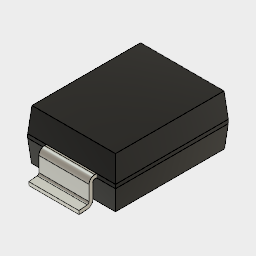
Untitled v1 (Autodesk Fusion 360 archive; units mm, degrees)
design "TSOP-2 4mm"
Autodesk Fusion 360 part; units mm, degrees
ref_plane "WorkPlane1" through (0, 0, 0.925) normal (0, 0, 1) x (1, 0, 0)
sketch "Sketch1" plane through (0, 0, 0.925) normal (0, 0, 1) x (1, 0, 0)
  line L0 (1.75, 2.25) -> (-1.75, 2.25)
  line L1 (-1.75, 2.25) -> (-1.75, -2.25)
  line L2 (-1.75, -2.25) -> (1.75, -2.25)
  line L3 (1.75, -2.25) -> (1.75, 2.25)
  line L4 (1.75, 2.25) -> (-1.75, -2.25) construction
  line L5 (-1.75, 2.25) -> (1.75, -2.25) construction
  dimension "d2" = 3.5
  dimension "d3" = 4.5
  measures "d2" distance of L1.end L2.end
  measures "d3" distance of L0.end L1.end
extrude "Extrude1" add sketch "Sketch1" against normal blind 0.875 draft -5 makes body 1
extrude "Extrude3" add sketch "Sketch1" along normal blind 0.15 bodies 1
extrude "Extrude4" add sketch "Sketch1" along normal blind 0.975 draft -5 from surface at 0.15 bodies 1
sketch "Sketch2" plane through (0, -2.25, 0) normal (0, -1, 0) x (1, 0, 0)
  line L0 (1.4672, 0.1123) -> (1.5, 0.4887)
  line L1 (1, 0.925) -> (-1, 0.925)
  line L2 (-1, 0.925) -> (-1, 1.075)
  line L3 (-1, 1.075) -> (1, 1.075)
  line L4 (1, 1.075) -> (1, 0.925)
  line L5 (1, 0.925) -> (-1, 1.075) construction
  line L6 (-1, 0.925) -> (1, 1.075) construction
  line L7 (-1.75, 0.925) -> (1.75, 0.925)
  line L8 (1.75, 0.925) -> (1.75, 1.075)
  line L9 (1.75, 1.075) -> (-1.75, 1.075)
  line L10 (-1.75, 1.075) -> (-1.75, 0.925)
  point P0 (0, 1)
  dimension "d6" = 2
  dimension "d7" = 0.15
  dimension "d51" = 1
  measures "d6" distance of L2.end L3.end
  measures "d7" distance of L1.end L2.end
  measures "d51" distance of origin P0
sketch "Sketch3" plane through (0, 0, 0) normal (1, 0, 0) x (0, 1, 0)
  line L0 (-2.25, 1) -> (-2.325, 1)
  arc A0 (-2.325, 1) -> (-2.475, 0.85) centre (-2.325, 0.85) ccw
  line L1 (-2.475, 0.85) -> (-2.475, 0.254)
  arc A1 (-2.6119, 0.1046) -> (-2.475, 0.254) centre (-2.625, 0.254) ccw
  line L2 (-2.6119, 0.1046) -> (-2.95, 0.075)
  line L3 (-2.25, 1.075) -> (-2.25, 0.925)
  line L4 (-2.25, 1) -> (-2.1, 1)
  line L5 (-2.95, 0.075) -> (-2.45, 0.075) construction
  point P0 (-2.25, 1)
  dimension "d10" = 0.15
  dimension "d11" = 0.075
  dimension "d21" = 0.15
  dimension "d22" = 0.225
  dimension "d23" = 0.7
  dimension "d24" = 0.5
  dimension "d25" = 5
  dimension "d26" = 0.15
  measures "d10" radius of A0
  measures "d11" distance of origin L2.end
  measures "d21" distance of P0 L4.end
  measures "d22" distance of P0 L1
  measures "d23" distance of P0 L2.end
  measures "d24" distance of L2.end L5.end
  measures "d25" angle of L2 L5
  measures "d26" radius of A1
sweep "Sweep1" add profiles "Sketch2" path "Sketch3" along L2 A1 L1 A0 L0 L4 section 1 contours L1 L2 L3 L4 L7 L9 separate body makes body 2
mirror "Mirror1" about plane through (0, 0, 0) normal (0, 1, 0) of "Sweep1" makes body 3
equation "d1 = tsop2_4_lead_attach - tsop2_4_lead_thickness / 2"
equation "d2 = tsop2_4_package_width"
equation "d3 = tsop2_4_package_depth"
equation "d4 = -tsop2_4_lead_attach + tsop2_4_lead_thickness / 2 + tsop2_4_above_board"
equation "d5 = -tsop2_4_package_taper"
equation "d6 = tsop2_4_lead_width"
equation "d7 = tsop2_4_lead_thickness"
equation "d10 = tsop2_4_lead_thickness"
equation "d11 = tsop2_4_lead_thickness / 2"
equation "tsop2_4_lead_thickness = 0.15 mm"
equation "tsop2_4_lead_attach = 1 mm"
equation "tsop2_4_lead_width = 2 mm"
equation "tsop2_4_lead_spacing = 1 mm"
equation "tsop2_4_package_width = 3.5 mm"
equation "tsop2_4_package_height = 2 mm"
equation "tsop2_4_package_depth = 4.5 mm"
equation "tsop2_4_above_board = 0.05 mm"
equation "d21 = tsop2_4_lead_into_package"
equation "d22 = tsop2_4_lead_thickness * ( 3 / 2 )"
equation "d23 = tsop2_4_lead_extension"
equation "d25 = tsop2_4_lead_foot_angle"
equation "d26 = d10"
equation "tsop2_4_lead_extension = 0.7 mm"
equation "tsop2_4_lead_foot_angle = 5 deg"
equation "tsop2_4_lead_into_package = 0.15 mm"
equation "tsop2_4_optional_lead_extension = 0 mm"
equation "tsop2_4_package_taper = 5 deg"
equation "d46 = tsop2_4_lead_thickness"
equation "d48 = tsop2_4_lead_thickness"
equation "d49 = tsop2_4_package_height - tsop2_4_lead_thickness / 2 - ( tsop2_4_lead_attach - tsop2_4_above_board )"
equation "d50 = -tsop2_4_package_taper"
equation "d51 = tsop2_4_lead_attach"
named bodies: "lead2", "opt_lead"

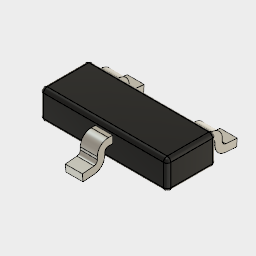
design "SOP-3 2.5mm"
Autodesk Fusion 360 part; units mm, degrees
ref_plane "WorkPlane1" through (0, 0, 0.05) normal (0, 0, 1) x (1, 0, 0)
sketch "Sketch1" plane through (0, 0, 0.05) normal (0, 0, 1) x (1, 0, 0)
  line L0 (1.3, 0.5) -> (-1.3, 0.5)
  line L1 (-1.3, 0.5) -> (-1.3, -0.5)
  line L2 (-1.3, -0.5) -> (1.3, -0.5)
  line L3 (1.3, -0.5) -> (1.3, 0.5)
  line L4 (1.3, 0.5) -> (-1.3, -0.5) construction
  line L5 (-1.3, 0.5) -> (1.3, -0.5) construction
  dimension "d2" = 2.6
  dimension "d3" = 1
  measures "d2" distance of L1.end L2.end
  measures "d3" distance of L0.end L1.end
extrude "Extrude1" add sketch "Sketch1" along normal blind 0.6 makes body 1
sketch "Sketch2" plane through (0, -0.5, 0) normal (0, -1, 0) x (1, 0, 0)
  line L0 (-1.3, 0.05) -> (1.3, 0.05)
  line L1 (1.3, 0.05) -> (1.3, 0.65)
  line L2 (1.3, 0.65) -> (-1.3, 0.65)
  line L3 (-1.3, 0.65) -> (-1.3, 0.05)
  line L4 (0.175, 0.375) -> (-0.175, 0.375)
  line L5 (-0.175, 0.375) -> (-0.175, 0.525)
  line L6 (-0.175, 0.525) -> (0.175, 0.525)
  line L7 (0.175, 0.525) -> (0.175, 0.375)
  line L8 (0.175, 0.375) -> (-0.175, 0.525) construction
  line L9 (-0.175, 0.375) -> (0.175, 0.525) construction
  point P0 (0, 0.45)
  dimension "d6" = 0.35
  dimension "d7" = 0.15
  dimension "d8" = 0.4
  measures "d6" distance of L5.end L6.end
  measures "d7" distance of L4.end L5.end
  measures "d8" distance of L0 P0
sketch "Sketch3" plane through (0, 0, 0) normal (1, 0, 0) x (0, 1, 0)
  line L0 (-0.5, 0.45) -> (-0.575, 0.45)
  arc A0 (-0.575, 0.45) -> (-0.725, 0.3) centre (-0.575, 0.3) ccw
  line L1 (-0.725, 0.3) -> (-0.725, 0.2453)
  arc A1 (-0.8619, 0.0958) -> (-0.725, 0.2453) centre (-0.875, 0.2453) ccw
  line L2 (-0.8619, 0.0958) -> (-1.1, 0.075)
  line L3 (-0.5, 0.525) -> (-0.5, 0.375)
  line L4 (-0.5, 0.45) -> (-0.4, 0.45)
  line L5 (-1.1, 0.075) -> (-0.6, 0.075) construction
  point P0 (-0.5, 0.45)
  dimension "d10" = 0.15
  dimension "d11" = 0.075
  dimension "d21" = 0.1
  dimension "d22" = 0.225
  dimension "d23" = 0.6
  dimension "d24" = 0.5
  dimension "d25" = 5
  dimension "d26" = 0.15
  measures "d10" radius of A0
  measures "d11" distance of origin L2.end
  measures "d21" distance of P0 L4.end
  measures "d22" distance of P0 L1
  measures "d23" distance of P0 L2.end
  measures "d24" distance of L2.end L5.end
  measures "d25" angle of L2 L5
  measures "d26" radius of A1
sweep "Sweep1" add profiles "Sketch2" path "Sketch3" along L2 A1 L1 A0 L0 L4 section 1 contours L4 L5 L6 L7 separate body makes body 2
pattern_linear "R-Pattern1" count 3 spacing 0.95 along (1, 0, 0) both ways of "Sweep1" makes body 3 at (-0.8917, -0.7997, 0.3107) makes body 4 at (1.0083, -0.7997, 0.3107)
fillet "Fillet1" radius 0.075 12 edges at (1.3, 0, 0.65) (0, -0.5, 0.65) (-1.3, 0, 0.65) (0, 0.5, 0.65) (1.3, -0.5, 0.35) (1.3, 0, 0.05) (1.3, 0.5, 0.35) (0, -0.5, 0.05) (-1.3, -0.5, 0.35) (-1.3, 0, 0.05) (0, 0.5, 0.05) (-1.3, 0.5, 0.35) on bodies 1
move_body "Move1" bodies 3 4 to x (-1, 0, 0) y (0, -1, 0) z (0, 0, 1) at (0, 0, 0)
equation "d1 = sop3_2_above_board"
equation "d2 = sop3_2_package_width"
equation "d3 = sop3_2_package_depth"
equation "d4 = sop3_2_package_height"
equation "d6 = sop3_2_lead_width"
equation "d7 = sop3_2_lead_thickness"
equation "d8 = sop3_2_lead_attach"
equation "d10 = sop3_2_lead_thickness"
equation "d11 = sop3_2_lead_thickness / 2"
equation "sop3_2_lead_thickness = 0.15 mm"
equation "sop3_2_lead_attach = 0.4 mm"
equation "sop3_2_lead_width = 0.35 mm"
equation "sop3_2_lead_spacing = 0.95 mm"
equation "sop3_2_package_width = 2.6 mm"
equation "sop3_2_package_height = 0.6 mm"
equation "sop3_2_package_depth = 1 mm"
equation "sop3_2_above_board = 0.05 mm"
equation "d21 = sop3_2_lead_into_package"
equation "d22 = sop3_2_lead_thickness * ( 3 / 2 )"
equation "d23 = sop3_2_lead_extension"
equation "d25 = sop3_2_lead_foot_angle"
equation "d26 = d10"
equation "sop3_2_lead_extension = 0.6 mm"
equation "sop3_2_lead_foot_angle = 5 deg"
equation "sop3_2_lead_into_package = 0.1 mm"
equation "d34 = sop3_2_lead_spacing"
equation "sop3_2_optional_lead_extension = 0 mm"
named bodies: "lead2", "lead1", "lead3"

design "SOP-3"
Autodesk Fusion 360 part; units mm, degrees
ref_plane "WorkPlane1" through (0, 0, 0.05) normal (0, 0, 1) x (1, 0, 0)
sketch "Sketch1" plane through (0, 0, 0.05) normal (0, 0, 1) x (1, 0, 0)
  line L0 (1.5, 0.75) -> (-1.5, 0.75)
  line L1 (-1.5, 0.75) -> (-1.5, -0.75)
  line L2 (-1.5, -0.75) -> (1.5, -0.75)
  line L3 (1.5, -0.75) -> (1.5, 0.75)
  line L4 (1.5, 0.75) -> (-1.5, -0.75) construction
  line L5 (-1.5, 0.75) -> (1.5, -0.75) construction
  dimension "d2" = 3
  dimension "d3" = 1.5
  measures "d2" distance of L1.end L2.end
  measures "d3" distance of L0.end L1.end
extrude "Extrude1" add sketch "Sketch1" along normal blind 1 makes body 1
sketch "Sketch2" plane through (0, -0.75, 0) normal (0, -1, 0) x (1, 0, 0)
  line L0 (-1.5, 0.05) -> (1.5, 0.05)
  line L1 (1.5, 0.05) -> (1.5, 1.05)
  line L2 (1.5, 1.05) -> (-1.5, 1.05)
  line L3 (-1.5, 1.05) -> (-1.5, 0.05)
  line L4 (0.175, 0.475) -> (-0.175, 0.475)
  line L5 (-0.175, 0.475) -> (-0.175, 0.625)
  line L6 (-0.175, 0.625) -> (0.175, 0.625)
  line L7 (0.175, 0.625) -> (0.175, 0.475)
  line L8 (0.175, 0.475) -> (-0.175, 0.625) construction
  line L9 (-0.175, 0.475) -> (0.175, 0.625) construction
  point P0 (0, 0.55)
  dimension "d6" = 0.35
  dimension "d7" = 0.15
  dimension "d8" = 0.5
  measures "d6" distance of L5.end L6.end
  measures "d7" distance of L4.end L5.end
  measures "d8" distance of L0 P0
sketch "Sketch3" plane through (0, 0, 0) normal (1, 0, 0) x (0, 1, 0)
  line L0 (-0.75, 0.55) -> (-0.825, 0.55)
  arc A0 (-0.825, 0.55) -> (-0.975, 0.4) centre (-0.825, 0.4) ccw
  line L1 (-0.975, 0.4) -> (-0.975, 0.2453)
  arc A1 (-1.1119, 0.0958) -> (-0.975, 0.2453) centre (-1.125, 0.2453) ccw
  line L2 (-1.1119, 0.0958) -> (-1.35, 0.075)
  line L3 (-0.75, 0.625) -> (-0.75, 0.475)
  line L4 (-0.75, 0.55) -> (-0.6, 0.55)
  line L5 (-1.35, 0.075) -> (-0.85, 0.075) construction
  point P0 (-0.75, 0.55)
  dimension "d10" = 0.15
  dimension "d11" = 0.075
  dimension "d21" = 0.15
  dimension "d22" = 0.225
  dimension "d23" = 0.6
  dimension "d24" = 0.5
  dimension "d25" = 5
  dimension "d26" = 0.15
  measures "d10" radius of A0
  measures "d11" distance of origin L2.end
  measures "d21" distance of P0 L4.end
  measures "d22" distance of P0 L1
  measures "d23" distance of P0 L2.end
  measures "d24" distance of L2.end L5.end
  measures "d25" angle of L2 L5
  measures "d26" radius of A1
sweep "Sweep1" add profiles "Sketch2" path "Sketch3" along L2 A1 L1 A0 L0 L4 section 1 contours L4 L5 L6 L7 separate body makes body 2
pattern_linear "R-Pattern1" count 3 spacing 0.95 along (1, 0, 0) both ways of "Sweep1" makes body 3 at (-1.0083, -1.049, 0.4214) makes body 4 at (0.8917, -1.049, 0.4214)
fillet "Fillet1" radius 0.075 12 edges at (1.5, 0, 1.05) (0, -0.75, 1.05) (-1.5, 0, 1.05) (0, 0.75, 1.05) (1.5, -0.75, 0.55) (1.5, 0, 0.05) (1.5, 0.75, 0.55) (0, -0.75, 0.05) (-1.5, -0.75, 0.55) (-1.5, 0, 0.05) (0, 0.75, 0.05) (-1.5, 0.75, 0.55) on bodies 1
move_body "Move1" bodies 3 4 to x (-1, 0, 0) y (0, -1, 0) z (0, 0, 1) at (0, 0, 0)
equation "d1 = sop3_above_board"
equation "d2 = sop3_package_width"
equation "d3 = sop3_package_depth"
equation "d4 = sop3_package_height"
equation "d6 = sop3_lead_width"
equation "d7 = sop3_lead_thickness"
equation "d8 = sop3_lead_attach"
equation "d10 = sop3_lead_thickness"
equation "d11 = sop3_lead_thickness / 2"
equation "sop3_lead_thickness = 0.15 mm"
equation "sop3_lead_attach = 0.5 mm"
equation "sop3_lead_width = 0.35 mm"
equation "sop3_lead_spacing = 0.95 mm"
equation "sop3_package_width = 3 mm"
equation "sop3_package_height = 1 mm"
equation "sop3_package_depth = 1.5 mm"
equation "sop3_above_board = 0.05 mm"
equation "d21 = sop3_lead_into_package"
equation "d22 = sop3_lead_thickness * ( 3 / 2 )"
equation "d23 = sop3_lead_extension"
equation "d25 = sop3_lead_foot_angle"
equation "d26 = d10"
equation "sop3_lead_extension = 0.6 mm"
equation "sop3_lead_foot_angle = 5 deg"
equation "sop3_lead_into_package = 0.15 mm"
equation "d34 = sop3_lead_spacing"
equation "sop3_optional_lead_extension = 0 mm"

design "capar2_1013"
Autodesk Fusion 360 part; units mm, degrees
ref_plane "WorkPlane4" through (0, 0, 0.02) normal (0, 0, 1) x (1, 0, 0)
sketch "Sketch5" plane through (0, 0, 0.02) normal (0, 0, 1) x (1, 0, 0)
  line L0 (0.65, -0.5) -> (-0.65, -0.5)
  line L1 (-0.65, -0.5) -> (-0.65, 0.5)
  line L2 (-0.65, 0.5) -> (0.65, 0.5)
  line L3 (0.65, 0.5) -> (0.65, -0.5)
  line L4 (0.65, -0.5) -> (-0.65, 0.5) construction
  line L5 (-0.65, -0.5) -> (0.65, 0.5) construction
  dimension "d38" = 1.3
  dimension "d39" = 1
  measures "d38" distance of L1.end L2.end
  measures "d39" distance of L0.end L1.end
extrude "Extrude4" add sketch "Sketch5" along normal blind 0.6 makes body 1
fillet "Fillet6" radius 0.03 12 edges at (-0.65, -0.5, 0.32) (-0.65, 0, 0.62) (0, 0.5, 0.62) (0, -0.5, 0.62) (-0.65, 0.5, 0.32) (-0.65, 0, 0.02) (0, -0.5, 0.02) (0, 0.5, 0.02) (0.65, 0, 0.62) (0.65, 0.5, 0.32) (0.65, -0.5, 0.32) (0.65, 0, 0.02) on bodies 1
sketch "Sketch7" plane through (0, 0, 0.02) normal (0, 0, 1) x (1, 0, 0)
  line L0 (-0.725, 0.4) -> (-0.275, 0.4)
  line L1 (-0.275, 0.4) -> (-0.275, 0.1)
  line L2 (-0.275, 0.1) -> (-0.725, 0.1)
  line L3 (-0.725, 0.1) -> (-0.725, 0.4)
  line L4 (0, 0) -> (-0.5, 0) construction
  line L5 (0, 0) -> (0, 0.4016) construction
  line L6 (-0.275, -0.4) -> (-0.275, -0.1)
  line L7 (-0.275, -0.1) -> (-0.725, -0.1)
  line L8 (-0.725, -0.1) -> (-0.725, -0.4)
  line L9 (-0.725, -0.4) -> (-0.275, -0.4)
  line L10 (0.725, 0.4) -> (0.275, 0.4)
  line L11 (0.275, 0.4) -> (0.275, 0.1)
  line L12 (0.275, 0.1) -> (0.725, 0.1)
  line L13 (0.725, 0.1) -> (0.725, 0.4)
  line L14 (0.725, -0.4) -> (0.275, -0.4)
  line L15 (0.275, -0.4) -> (0.275, -0.1)
  line L16 (0.725, -0.1) -> (0.725, -0.4)
  line L17 (0.275, -0.1) -> (0.725, -0.1)
  line L18 (-0.68, 0.4) -> (-0.68, 0.1)
  line L19 (-0.68, -0.1) -> (-0.68, -0.4)
  line L20 (-0.62, 0.4) -> (-0.62, 0.1)
  line L21 (-0.62, -0.1) -> (-0.62, -0.4)
  line L22 (0.68, 0.4) -> (0.68, 0.1)
  line L23 (0.62, 0.4) -> (0.62, 0.1)
  line L24 (0.68, -0.1) -> (0.68, -0.4)
  line L25 (0.62, -0.1) -> (0.62, -0.4)
  dimension "d41" = 0.45
  dimension "d42" = 0.3
  dimension "d43" = 1
  dimension "d44" = 0.5
  dimension "d45" = 0.62
  dimension "d46" = 0.06
  measures "d41" distance of L0.start L0.end
  measures "d42" distance of L0.start L2.end
  measures "d43" distance of L1 L13
  measures "d44" distance of L2 L9
  measures "d45" distance of L4.start L20
  measures "d46" distance of L18 L20
extrude "Extrude8" add sketch "Sketch7" against normal blind 0.02 separate body makes body 2 at (0.425, 0.3, 0.02) makes body 3 at (0.575, -0.3, 0.02) makes body 4 at (-0.575, 0.3, 0.02) makes body 5 at (-0.425, -0.3, 0.02)
extrude "Extrude9" add sketch "Sketch7" along normal blind 0.6 contours L0 L2 L18 L20 | L7 L9 L19 L21 | L10 L12 L22 L23 | L14 L17 L24 L25 bodies 2 3 4 5
sketch "Sketch6" plane through (0, 0, 0.62) normal (0, 0, 1) x (-1, 0, 0)
  line L0 (0, 0) -> (0.35, 0) construction
  line L1 (0, 0) -> (0, -0.4804) construction
  line L2 (0.68, 0.1) -> (0.48, 0.1)
  line L3 (0.48, 0.1) -> (0.48, 0.4)
  line L4 (0.48, 0.4) -> (0.68, 0.4)
  line L5 (0.68, 0.4) -> (0.68, 0.1)
  line L6 (0.68, -0.4) -> (0.68, -0.1)
  line L7 (0.68, -0.1) -> (0.48, -0.1)
  line L8 (0.48, -0.1) -> (0.48, -0.4)
  line L9 (0.48, -0.4) -> (0.68, -0.4)
  line L10 (-0.48, -0.1) -> (-0.48, -0.4)
  line L11 (-0.48, -0.4) -> (-0.68, -0.4)
  line L12 (-0.68, -0.4) -> (-0.68, -0.1)
  line L13 (-0.68, -0.1) -> (-0.48, -0.1)
  line L14 (-0.68, 0.4) -> (-0.68, 0.1)
  line L15 (-0.68, 0.1) -> (-0.48, 0.1)
  line L16 (-0.48, 0.4) -> (-0.68, 0.4)
  line L17 (-0.48, 0.1) -> (-0.48, 0.4)
  line L18 (0.68, 0.1) -> (0.68, 0.4)
  line L19 (0.68, 0.4) -> (0.62, 0.4)
  line L20 (0.62, 0.1) -> (0.68, 0.1)
  point P0 (0.68, 0.4)
  dimension "d51" = 0.2
  measures "d51" distance of L3 L5
extrude "Extrude7" add sketch "Sketch6" along normal blind 0.03 bodies 2 3 4 5
fillet "Fillet5" radius 0.3 4 edges at (0.68, 0.25, 0.02) (0.68, -0.25, 0.02) (-0.68, 0.25, 0.02) (-0.68, -0.25, 0.02) on bodies 2 3 4 5
fillet "Fillet5" radius 0.075 12 edges at (0.48, 0.1, 0.635) (0.48, 0.4, 0.635) (0.68, 0.25, 0.65) (0.68, -0.25, 0.65) (0.48, -0.4, 0.635) (0.48, -0.1, 0.635) (-0.68, 0.25, 0.65) (-0.48, 0.1, 0.635) (-0.48, 0.4, 0.635) (-0.48, -0.4, 0.635) (-0.48, -0.1, 0.635) (-0.68, -0.25, 0.65) on bodies 2 3 4 5
fillet "Fillet7" radius 0.02 44 edges at (0.6915, 0.1, 0.0959) (0.68, 0.1, 0.3765) (0.658, 0.1, 0.628) (0.58, 0.1, 0.65) (0.502, 0.122, 0.65) (0.48, 0.25, 0.65) (0.502, 0.378, 0.65) (0.58, 0.4, 0.65) (0.658, 0.4, 0.628) (0.68, 0.4, 0.3765) (0.6915, 0.4, 0.0959) (0.6915, -0.4, 0.0959) (0.68, -0.4, 0.3765) (0.658, -0.4, 0.628) (0.58, -0.4, 0.65) (0.502, -0.378, 0.65) (0.48, -0.25, 0.65) (0.502, -0.122, 0.65) (0.58, -0.1, 0.65) (0.658, -0.1, 0.628) (0.68, -0.1, 0.3765) (0.6915, -0.1, 0.0959) (-0.6915, 0.4, 0.0959) (-0.68, 0.4, 0.3765) (-0.658, 0.4, 0.628) (-0.58, 0.4, 0.65) (-0.502, 0.378, 0.65) (-0.48, 0.25, 0.65) (-0.502, 0.122, 0.65) (-0.58, 0.1, 0.65) (-0.658, 0.1, 0.628) (-0.68, 0.1, 0.3765) (-0.6915, 0.1, 0.0959) (-0.6915, -0.1, 0.0959) (-0.68, -0.1, 0.3765) (-0.658, -0.1, 0.628) (-0.58, -0.1, 0.65) (-0.502, -0.122, 0.65) (-0.48, -0.25, 0.65) (-0.502, -0.378, 0.65) (-0.58, -0.4, 0.65) (-0.658, -0.4, 0.628) (-0.68, -0.4, 0.3765) (-0.6915, -0.4, 0.0959) on bodies 2 3 4 5
equation "capar2_1310_height = 0.6 mm"
equation "capar2_1310_width = 1 mm"
equation "capar2_1310_length = 1.3 mm"
equation "capar2_1310_tin_len = 0.2 mm"
equation "capar2_1310_tin_thick_axial = 0.06 mm"
equation "capar2_1310_land_width_spacing = 0.5 mm"
equation "capar2_1310_land_width = 0.3 mm"
equation "capar2_1310_land_length = 0.45 mm"
equation "capar2_1310_above_board = 0.02 mm"
equation "d6 = capar2_1310_above_board"
equation "capar2_1310_land_length_spacing = 1 mm"
equation "d17 = capar2_1310_height"
equation "d26 = capar2_1310_tin_thick_axial / 2"
equation "d38 = capar2_1310_length"
equation "d39 = capar2_1310_width"
equation "d41 = capar2_1310_land_length"
equation "d42 = capar2_1310_land_width"
equation "d43 = capar2_1310_land_length_spacing"
equation "d44 = capar2_1310_land_width_spacing"
equation "d45 = capar2_1310_length / 2 - capar2_1310_tin_thick_axial / 2"
equation "d46 = capar2_1310_tin_thick_axial"
equation "d47 = -capar2_1310_above_board"
equation "d49 = capar2_1310_height"
equation "d51 = capar2_1310_tin_len"
equation "d52 = capar2_1310_height / 2"
